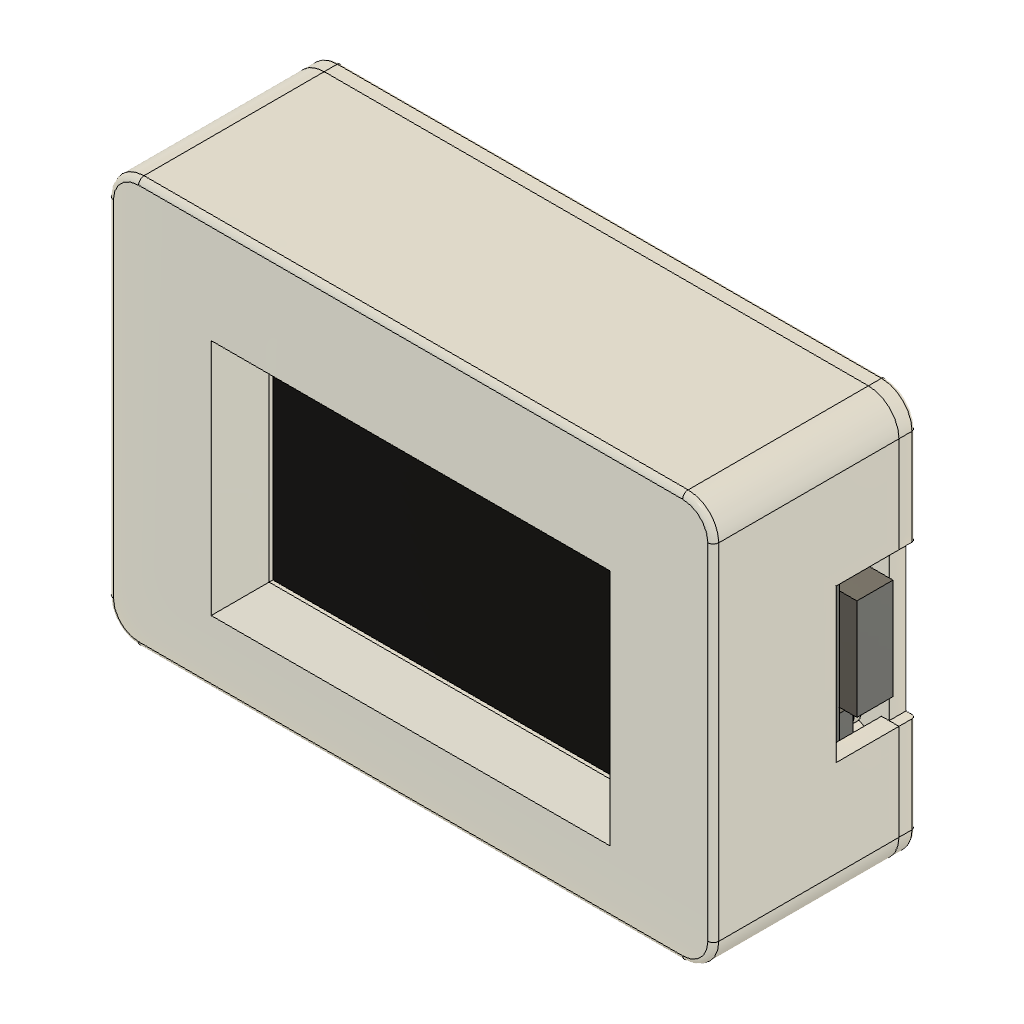
rocket-oled-tall-bezel-case (Autodesk Fusion 360 design; units mm, degrees)
part number: 2026-11-09-02-39-56-259
part number: 2026-11-09-02-39-56-642
part number: 2026-11-09-02-39-58-519
part number: 2026-11-09-02-40-05-044
part number: 2026-11-09-02-40-06-860
part number: 2026-11-09-02-56-29-701
part number: 2026-11-09-03-49-20-319
part number: 2026-11-09-03-49-23-306
part number: 2026-11-09-03-52-10-311
Autodesk Fusion 360 part; units mm, degrees
(part 1 of 3)
ref_plane "WorkPlane1" through (0, 0, 1.55) normal (0, 0, 1) x (1, 0, 0) in component "01 Beveled front - four blind OLED screw bosses"
sketch "Outer shell profile" plane through (0, 0, 1.55) normal (0, 0, 1) x (1, 0, 0) in component "01 Beveled front - four blind OLED screw bosses"
  line L0 (-27.71, -18.6) -> (27.71, -18.6)
  line L1 (27.71, -18.6) -> (27.71, 18.6)
  line L2 (27.71, 18.6) -> (-27.71, 18.6)
  line L3 (-27.71, 18.6) -> (-27.71, -18.6)
  dimension "d81" = 27.71
  dimension "d82" = 18.6
  dimension "d83" = 55.42
  dimension "d84" = 37.2
  constraint horizontal L0
  constraint horizontal L2
  constraint vertical L1
  constraint vertical L3
  measures "d81" horizontal distance of origin L0.start
  measures "d82" vertical distance of origin L0.start
  measures "d83" horizontal distance of L0.start L0.end
  measures "d84" vertical distance of L0.end L1.end
extrude "Outer shell" add sketch "Outer shell profile" along normal blind 17 makes body 1 in component "01 Beveled front - four blind OLED screw bosses"
fillet "Rounded exterior corners" radius 2.8 4 edges at (-27.71, 18.6, 10.05) (27.71, 18.6, 10.05) (27.71, -18.6, 10.05) (-27.71, -18.6, 10.05) on bodies 1 in component "01 Beveled front - four blind OLED screw bosses"
fillet "Soft front edge" radius 0.5 8 edges at (-26.8899, -17.7799, 18.55) (-27.71, 0, 18.55) (0, -18.6, 18.55) (26.8899, -17.7799, 18.55) (27.71, 0, 18.55) (26.8899, 17.7799, 18.55) (0, 18.6, 18.55) (-26.8899, 17.7799, 18.55) on bodies 1 in component "01 Beveled front - four blind OLED screw bosses"
ref_plane "WorkPlane2" through (0, 0, 1.55) normal (0, 0, 1) x (1, 0, 0) in component "01 Beveled front - four blind OLED screw bosses"
sketch "Open rear cavity profile" plane through (0, 0, 1.55) normal (0, 0, 1) x (1, 0, 0) in component "01 Beveled front - four blind OLED screw bosses"
  line L0 (-26.11, -17) -> (26.11, -17)
  line L1 (26.11, -17) -> (26.11, 17)
  line L2 (26.11, 17) -> (-26.11, 17)
  line L3 (-26.11, 17) -> (-26.11, -17)
  dimension "d93" = 26.11
  dimension "d94" = 17
  dimension "d95" = 52.22
  dimension "d96" = 34
  constraint horizontal L0
  constraint horizontal L2
  constraint vertical L1
  constraint vertical L3
  measures "d93" horizontal distance of origin L0.start
  measures "d94" vertical distance of origin L0.start
  measures "d95" horizontal distance of L0.start L0.end
  measures "d96" vertical distance of L0.end L1.end
extrude "Open rear cavity" cut sketch "Open rear cavity profile" along normal blind 12.4 bodies 1 in component "01 Beveled front - four blind OLED screw bosses"
fillet "Rounded cavity corners" radius 1.2 4 edges at (26.11, 17, 7.75) (-26.11, 17, 7.75) (26.11, -17, 7.75) (-26.11, -17, 7.75) on bodies 1 in component "01 Beveled front - four blind OLED screw bosses"
ref_plane "WorkPlane3" through (0, 0, 13.95) normal (0, 0, 1) x (1, 0, 0) in component "01 Beveled front - four blind OLED screw bosses"
sketch "OLED glass relief profile" plane through (0, 0, 13.95) normal (0, 0, 1) x (1, 0, 0) in component "01 Beveled front - four blind OLED screw bosses"
  line L0 (-17.55, -11.8) -> (17.55, -11.8)
  line L1 (17.55, -11.8) -> (17.55, 11.8)
  line L2 (17.55, 11.8) -> (-17.55, 11.8)
  line L3 (-17.55, 11.8) -> (-17.55, -11.8)
  dimension "d103" = 17.55
  dimension "d104" = 11.8
  dimension "d105" = 35.1
  dimension "d106" = 23.6
  constraint horizontal L0
  constraint horizontal L2
  constraint vertical L1
  constraint vertical L3
  measures "d103" horizontal distance of origin L0.start
  measures "d104" vertical distance of origin L0.start
  measures "d105" horizontal distance of L0.start L0.end
  measures "d106" vertical distance of L0.end L1.end
extrude "Glass clearance beneath concealed wiring bezel" cut sketch "OLED glass relief profile" along normal blind 1.6 bodies 1 in component "01 Beveled front - four blind OLED screw bosses"
ref_plane "WorkPlane4" through (0, 0, 15.55) normal (0, 0, 1) x (1, 0, 0) in component "01 Beveled front - four blind OLED screw bosses"
sketch "OLED active-area window profile" plane through (0, 0, 15.55) normal (0, 0, 1) x (1, 0, 0) in component "01 Beveled front - four blind OLED screw bosses"
  line L0 (-15.61, -10.05) -> (15.61, -10.05)
  line L1 (15.61, -10.05) -> (15.61, 6.45)
  line L2 (15.61, 6.45) -> (-15.61, 6.45)
  line L3 (-15.61, 6.45) -> (-15.61, -10.05)
  dimension "d111" = 15.61
  dimension "d112" = 10.05
  dimension "d113" = 31.22
  dimension "d114" = 16.5
  constraint horizontal L0
  constraint horizontal L2
  constraint vertical L1
  constraint vertical L3
  measures "d111" horizontal distance of origin L0.start
  measures "d112" vertical distance of origin L0.start
  measures "d113" horizontal distance of L0.start L0.end
  measures "d114" vertical distance of L0.end L1.end
ref_plane "WorkPlane5" through (0, 0, 13.45) normal (0, 0, 1) x (1, 0, 0) in component "01 Beveled front - four blind OLED screw bosses"
sketch "OLED PCB bearing pads 1 profile" plane through (0, 0, 13.45) normal (0, 0, 1) x (1, 0, 0) in component "01 Beveled front - four blind OLED screw bosses"
  circle A0 centre (-15.2, -14.25) radius 2.3
  dimension "d119" = 15.2
  dimension "d120" = 14.25
  dimension "d121" = 4.6
  measures "d119" horizontal distance of origin A0.centre
  measures "d120" vertical distance of origin A0.centre
  measures "d121" diameter of A0
extrude "OLED PCB bearing pads 1" add sketch "OLED PCB bearing pads 1 profile" along normal blind 0.5 bodies 1 in component "01 Beveled front - four blind OLED screw bosses"
ref_plane "WorkPlane6" through (0, 0, 13.45) normal (0, 0, 1) x (1, 0, 0) in component "01 Beveled front - four blind OLED screw bosses"
sketch "OLED PCB bearing pads 2 profile" plane through (0, 0, 13.45) normal (0, 0, 1) x (1, 0, 0) in component "01 Beveled front - four blind OLED screw bosses"
  circle A0 centre (-15.2, 14.25) radius 2.3
  dimension "d126" = 15.2
  dimension "d127" = 14.25
  dimension "d128" = 4.6
  measures "d126" horizontal distance of origin A0.centre
  measures "d127" vertical distance of origin A0.centre
  measures "d128" diameter of A0
extrude "OLED PCB bearing pads 2" add sketch "OLED PCB bearing pads 2 profile" along normal blind 0.5 bodies 1 in component "01 Beveled front - four blind OLED screw bosses"
ref_plane "WorkPlane7" through (0, 0, 13.45) normal (0, 0, 1) x (1, 0, 0) in component "01 Beveled front - four blind OLED screw bosses"
sketch "OLED PCB bearing pads 3 profile" plane through (0, 0, 13.45) normal (0, 0, 1) x (1, 0, 0) in component "01 Beveled front - four blind OLED screw bosses"
  circle A0 centre (15.2, -14.25) radius 2.3
  dimension "d133" = 15.2
  dimension "d134" = 14.25
  dimension "d135" = 4.6
  measures "d133" horizontal distance of origin A0.centre
  measures "d134" vertical distance of origin A0.centre
  measures "d135" diameter of A0
extrude "OLED PCB bearing pads 3" add sketch "OLED PCB bearing pads 3 profile" along normal blind 0.5 bodies 1 in component "01 Beveled front - four blind OLED screw bosses"
ref_plane "WorkPlane8" through (0, 0, 13.45) normal (0, 0, 1) x (1, 0, 0) in component "01 Beveled front - four blind OLED screw bosses"
sketch "OLED PCB bearing pads 4 profile" plane through (0, 0, 13.45) normal (0, 0, 1) x (1, 0, 0) in component "01 Beveled front - four blind OLED screw bosses"
  circle A0 centre (15.2, 14.25) radius 2.3
  dimension "d140" = 15.2
  dimension "d141" = 14.25
  dimension "d142" = 4.6
  measures "d140" horizontal distance of origin A0.centre
  measures "d141" vertical distance of origin A0.centre
  measures "d142" diameter of A0
extrude "OLED PCB bearing pads 4" add sketch "OLED PCB bearing pads 4 profile" along normal blind 0.5 bodies 1 in component "01 Beveled front - four blind OLED screw bosses"
ref_plane "WorkPlane9" through (0, 0, 11.9) normal (0, 0, 1) x (1, 0, 0) in component "01 Beveled front - four blind OLED screw bosses"
sketch "OLED left lower edge stop profile" plane through (0, 0, 11.9) normal (0, 0, 1) x (1, 0, 0) in component "01 Beveled front - four blind OLED screw bosses"
  line L0 (-19.45, -10.5) -> (-17.95, -10.5)
  line L1 (-17.95, -10.5) -> (-17.95, -6.5)
  line L2 (-17.95, -6.5) -> (-19.45, -6.5)
  line L3 (-19.45, -6.5) -> (-19.45, -10.5)
  dimension "d147" = 19.45
  dimension "d148" = 10.5
  dimension "d149" = 1.5
  dimension "d150" = 4
  constraint horizontal L0
  constraint horizontal L2
  constraint vertical L1
  constraint vertical L3
  measures "d147" horizontal distance of origin L0.start
  measures "d148" vertical distance of origin L0.start
  measures "d149" horizontal distance of L0.start L0.end
  measures "d150" vertical distance of L0.end L1.end
extrude "OLED left lower edge stop" add sketch "OLED left lower edge stop profile" along normal blind 2.05 bodies 1 in component "01 Beveled front - four blind OLED screw bosses"
ref_plane "WorkPlane10" through (0, 0, 11.9) normal (0, 0, 1) x (1, 0, 0) in component "01 Beveled front - four blind OLED screw bosses"
sketch "OLED left upper edge stop profile" plane through (0, 0, 11.9) normal (0, 0, 1) x (1, 0, 0) in component "01 Beveled front - four blind OLED screw bosses"
  line L0 (-19.45, 6.5) -> (-17.95, 6.5)
  line L1 (-17.95, 6.5) -> (-17.95, 10.5)
  line L2 (-17.95, 10.5) -> (-19.45, 10.5)
  line L3 (-19.45, 10.5) -> (-19.45, 6.5)
  dimension "d155" = 19.45
  dimension "d156" = 6.5
  dimension "d157" = 1.5
  dimension "d158" = 4
  constraint horizontal L0
  constraint horizontal L2
  constraint vertical L1
  constraint vertical L3
  measures "d155" horizontal distance of origin L0.start
  measures "d156" vertical distance of origin L0.start
  measures "d157" horizontal distance of L0.start L0.end
  measures "d158" vertical distance of L0.end L1.end
extrude "OLED left upper edge stop" add sketch "OLED left upper edge stop profile" along normal blind 2.05 bodies 1 in component "01 Beveled front - four blind OLED screw bosses"
ref_plane "WorkPlane11" through (0, 0, 11.9) normal (0, 0, 1) x (1, 0, 0) in component "01 Beveled front - four blind OLED screw bosses"
sketch "OLED right lower edge stop profile" plane through (0, 0, 11.9) normal (0, 0, 1) x (1, 0, 0) in component "01 Beveled front - four blind OLED screw bosses"
  line L0 (17.95, -10.5) -> (19.45, -10.5)
  line L1 (19.45, -10.5) -> (19.45, -6.5)
  line L2 (19.45, -6.5) -> (17.95, -6.5)
  line L3 (17.95, -6.5) -> (17.95, -10.5)
  dimension "d163" = 17.95
  dimension "d164" = 10.5
  dimension "d165" = 1.5
  dimension "d166" = 4
  constraint horizontal L0
  constraint horizontal L2
  constraint vertical L1
  constraint vertical L3
  measures "d163" horizontal distance of origin L0.start
  measures "d164" vertical distance of origin L0.start
  measures "d165" horizontal distance of L0.start L0.end
  measures "d166" vertical distance of L0.end L1.end
extrude "OLED right lower edge stop" add sketch "OLED right lower edge stop profile" along normal blind 2.05 bodies 1 in component "01 Beveled front - four blind OLED screw bosses"
ref_plane "WorkPlane12" through (0, 0, 11.9) normal (0, 0, 1) x (1, 0, 0) in component "01 Beveled front - four blind OLED screw bosses"
sketch "OLED right upper edge stop profile" plane through (0, 0, 11.9) normal (0, 0, 1) x (1, 0, 0) in component "01 Beveled front - four blind OLED screw bosses"
  line L0 (17.95, 6.5) -> (19.45, 6.5)
  line L1 (19.45, 6.5) -> (19.45, 10.5)
  line L2 (19.45, 10.5) -> (17.95, 10.5)
  line L3 (17.95, 10.5) -> (17.95, 6.5)
  dimension "d171" = 17.95
  dimension "d172" = 6.5
  dimension "d173" = 1.5
  dimension "d174" = 4
  constraint horizontal L0
  constraint horizontal L2
  constraint vertical L1
  constraint vertical L3
  measures "d171" horizontal distance of origin L0.start
  measures "d172" vertical distance of origin L0.start
  measures "d173" horizontal distance of L0.start L0.end
  measures "d174" vertical distance of L0.end L1.end
extrude "OLED right upper edge stop" add sketch "OLED right upper edge stop profile" along normal blind 2.05 bodies 1 in component "01 Beveled front - four blind OLED screw bosses"
ref_plane "WorkPlane13" through (0, 0, 6.85) normal (0, 0, 1) x (1, 0, 0) in component "01 Beveled front - four blind OLED screw bosses"
sketch "Shared M2 shell and ESP32 bosses 1 profile" plane through (0, 0, 6.85) normal (0, 0, 1) x (1, 0, 0) in component "01 Beveled front - four blind OLED screw bosses"
  circle A0 centre (-23.09, -11.2) radius 2.6
  dimension "d179" = 23.09
  dimension "d180" = 11.2
  dimension "d181" = 5.2
  measures "d179" horizontal distance of origin A0.centre
  measures "d180" vertical distance of origin A0.centre
  measures "d181" diameter of A0
extrude "Shared M2 shell and ESP32 bosses 1" add sketch "Shared M2 shell and ESP32 bosses 1 profile" along normal blind 7.1 bodies 1 in component "01 Beveled front - four blind OLED screw bosses"
ref_plane "WorkPlane14" through (0, 0, 6.85) normal (0, 0, 1) x (1, 0, 0) in component "01 Beveled front - four blind OLED screw bosses"
sketch "Shared M2 shell and ESP32 bosses 2 profile" plane through (0, 0, 6.85) normal (0, 0, 1) x (1, 0, 0) in component "01 Beveled front - four blind OLED screw bosses"
  circle A0 centre (-23.09, 11.2) radius 2.6
  dimension "d186" = 23.09
  dimension "d187" = 11.2
  dimension "d188" = 5.2
  measures "d186" horizontal distance of origin A0.centre
  measures "d187" vertical distance of origin A0.centre
  measures "d188" diameter of A0
extrude "Shared M2 shell and ESP32 bosses 2" add sketch "Shared M2 shell and ESP32 bosses 2 profile" along normal blind 7.1 bodies 1 in component "01 Beveled front - four blind OLED screw bosses"
ref_plane "WorkPlane15" through (0, 0, 6.85) normal (0, 0, 1) x (1, 0, 0) in component "01 Beveled front - four blind OLED screw bosses"
sketch "Shared M2 shell and ESP32 bosses 3 profile" plane through (0, 0, 6.85) normal (0, 0, 1) x (1, 0, 0) in component "01 Beveled front - four blind OLED screw bosses"
  circle A0 centre (23.09, -11.2) radius 2.6
  dimension "d193" = 23.09
  dimension "d194" = 11.2
  dimension "d195" = 5.2
  measures "d193" horizontal distance of origin A0.centre
  measures "d194" vertical distance of origin A0.centre
  measures "d195" diameter of A0
extrude "Shared M2 shell and ESP32 bosses 3" add sketch "Shared M2 shell and ESP32 bosses 3 profile" along normal blind 7.1 bodies 1 in component "01 Beveled front - four blind OLED screw bosses"
ref_plane "WorkPlane16" through (0, 0, 6.85) normal (0, 0, 1) x (1, 0, 0) in component "01 Beveled front - four blind OLED screw bosses"
sketch "Shared M2 shell and ESP32 bosses 4 profile" plane through (0, 0, 6.85) normal (0, 0, 1) x (1, 0, 0) in component "01 Beveled front - four blind OLED screw bosses"
  circle A0 centre (23.09, 11.2) radius 2.6
  dimension "d200" = 23.09
  dimension "d201" = 11.2
  dimension "d202" = 5.2
  measures "d200" horizontal distance of origin A0.centre
  measures "d201" vertical distance of origin A0.centre
  measures "d202" diameter of A0
extrude "Shared M2 shell and ESP32 bosses 4" add sketch "Shared M2 shell and ESP32 bosses 4 profile" along normal blind 7.1 bodies 1 in component "01 Beveled front - four blind OLED screw bosses"
ref_plane "WorkPlane17" through (0, 0, 6.85) normal (0, 0, 1) x (1, 0, 0) in component "01 Beveled front - four blind OLED screw bosses"
sketch "left lower screw boss reinforcement profile" plane through (0, 0, 6.85) normal (0, 0, 1) x (1, 0, 0) in component "01 Beveled front - four blind OLED screw bosses"
  line L0 (-26.31, -12.65) -> (-23.09, -12.65)
  line L1 (-23.09, -12.65) -> (-23.09, -9.75)
  line L2 (-23.09, -9.75) -> (-26.31, -9.75)
  line L3 (-26.31, -9.75) -> (-26.31, -12.65)
  dimension "d207" = 26.31
  dimension "d208" = 12.65
  dimension "d209" = 3.22
  dimension "d210" = 2.9
  constraint horizontal L0
  constraint horizontal L2
  constraint vertical L1
  constraint vertical L3
  measures "d207" horizontal distance of origin L0.start
  measures "d208" vertical distance of origin L0.start
  measures "d209" horizontal distance of L0.start L0.end
  measures "d210" vertical distance of L0.end L1.end
extrude "left lower screw boss reinforcement" add sketch "left lower screw boss reinforcement profile" along normal blind 7.1 bodies 1 in component "01 Beveled front - four blind OLED screw bosses"
ref_plane "WorkPlane18" through (0, 0, 6.85) normal (0, 0, 1) x (1, 0, 0) in component "01 Beveled front - four blind OLED screw bosses"
sketch "left upper screw boss reinforcement profile" plane through (0, 0, 6.85) normal (0, 0, 1) x (1, 0, 0) in component "01 Beveled front - four blind OLED screw bosses"
  line L0 (-26.31, 9.75) -> (-23.09, 9.75)
  line L1 (-23.09, 9.75) -> (-23.09, 12.65)
  line L2 (-23.09, 12.65) -> (-26.31, 12.65)
  line L3 (-26.31, 12.65) -> (-26.31, 9.75)
  dimension "d215" = 26.31
  dimension "d216" = 9.75
  dimension "d217" = 3.22
  dimension "d218" = 2.9
  constraint horizontal L0
  constraint horizontal L2
  constraint vertical L1
  constraint vertical L3
  measures "d215" horizontal distance of origin L0.start
  measures "d216" vertical distance of origin L0.start
  measures "d217" horizontal distance of L0.start L0.end
  measures "d218" vertical distance of L0.end L1.end
extrude "left upper screw boss reinforcement" add sketch "left upper screw boss reinforcement profile" along normal blind 7.1 bodies 1 in component "01 Beveled front - four blind OLED screw bosses"
ref_plane "WorkPlane19" through (0, 0, 6.85) normal (0, 0, 1) x (1, 0, 0) in component "01 Beveled front - four blind OLED screw bosses"
sketch "right lower screw boss reinforcement profile" plane through (0, 0, 6.85) normal (0, 0, 1) x (1, 0, 0) in component "01 Beveled front - four blind OLED screw bosses"
  line L0 (23.09, -12.65) -> (26.31, -12.65)
  line L1 (26.31, -12.65) -> (26.31, -9.75)
  line L2 (26.31, -9.75) -> (23.09, -9.75)
  line L3 (23.09, -9.75) -> (23.09, -12.65)
  dimension "d223" = 23.09
  dimension "d224" = 12.65
  dimension "d225" = 3.22
  dimension "d226" = 2.9
  constraint horizontal L0
  constraint horizontal L2
  constraint vertical L1
  constraint vertical L3
  measures "d223" horizontal distance of origin L0.start
  measures "d224" vertical distance of origin L0.start
  measures "d225" horizontal distance of L0.start L0.end
  measures "d226" vertical distance of L0.end L1.end
extrude "right lower screw boss reinforcement" add sketch "right lower screw boss reinforcement profile" along normal blind 7.1 bodies 1 in component "01 Beveled front - four blind OLED screw bosses"
ref_plane "WorkPlane20" through (0, 0, 6.85) normal (0, 0, 1) x (1, 0, 0) in component "01 Beveled front - four blind OLED screw bosses"
sketch "right upper screw boss reinforcement profile" plane through (0, 0, 6.85) normal (0, 0, 1) x (1, 0, 0) in component "01 Beveled front - four blind OLED screw bosses"
  line L0 (23.09, 9.75) -> (26.31, 9.75)
  line L1 (26.31, 9.75) -> (26.31, 12.65)
  line L2 (26.31, 12.65) -> (23.09, 12.65)
  line L3 (23.09, 12.65) -> (23.09, 9.75)
  dimension "d231" = 23.09
  dimension "d232" = 9.75
  dimension "d233" = 3.22
  dimension "d234" = 2.9
  constraint horizontal L0
  constraint horizontal L2
  constraint vertical L1
  constraint vertical L3
  measures "d231" horizontal distance of origin L0.start
  measures "d232" vertical distance of origin L0.start
  measures "d233" horizontal distance of L0.start L0.end
  measures "d234" vertical distance of L0.end L1.end
extrude "right upper screw boss reinforcement" add sketch "right upper screw boss reinforcement profile" along normal blind 7.1 bodies 1 in component "01 Beveled front - four blind OLED screw bosses"
ref_plane "WorkPlane21" through (0, 0, 6.85) normal (0, 0, 1) x (1, 0, 0) in component "01 Beveled front - four blind OLED screw bosses"
sketch "Blind M2 pilot 1 profile" plane through (0, 0, 6.85) normal (0, 0, 1) x (1, 0, 0) in component "01 Beveled front - four blind OLED screw bosses"
  circle A0 centre (-23.09, -11.2) radius 0.85
  dimension "d239" = 23.09
  dimension "d240" = 11.2
  dimension "d241" = 1.7
  measures "d239" horizontal distance of origin A0.centre
  measures "d240" vertical distance of origin A0.centre
  measures "d241" diameter of A0
extrude "Blind M2 pilot 1" cut sketch "Blind M2 pilot 1 profile" along normal blind 4.45 bodies 1 in component "01 Beveled front - four blind OLED screw bosses"
ref_plane "WorkPlane22" through (0, 0, 6.85) normal (0, 0, 1) x (1, 0, 0) in component "01 Beveled front - four blind OLED screw bosses"
sketch "Blind M2 pilot 2 profile" plane through (0, 0, 6.85) normal (0, 0, 1) x (1, 0, 0) in component "01 Beveled front - four blind OLED screw bosses"
  circle A0 centre (-23.09, 11.2) radius 0.85
  dimension "d246" = 23.09
  dimension "d247" = 11.2
  dimension "d248" = 1.7
  measures "d246" horizontal distance of origin A0.centre
  measures "d247" vertical distance of origin A0.centre
  measures "d248" diameter of A0
extrude "Blind M2 pilot 2" cut sketch "Blind M2 pilot 2 profile" along normal blind 4.45 bodies 1 in component "01 Beveled front - four blind OLED screw bosses"
ref_plane "WorkPlane23" through (0, 0, 6.85) normal (0, 0, 1) x (1, 0, 0) in component "01 Beveled front - four blind OLED screw bosses"
sketch "Blind M2 pilot 3 profile" plane through (0, 0, 6.85) normal (0, 0, 1) x (1, 0, 0) in component "01 Beveled front - four blind OLED screw bosses"
  circle A0 centre (23.09, -11.2) radius 0.85
  dimension "d253" = 23.09
  dimension "d254" = 11.2
  dimension "d255" = 1.7
  measures "d253" horizontal distance of origin A0.centre
  measures "d254" vertical distance of origin A0.centre
  measures "d255" diameter of A0
extrude "Blind M2 pilot 3" cut sketch "Blind M2 pilot 3 profile" along normal blind 4.45 bodies 1 in component "01 Beveled front - four blind OLED screw bosses"
ref_plane "WorkPlane24" through (0, 0, 6.85) normal (0, 0, 1) x (1, 0, 0) in component "01 Beveled front - four blind OLED screw bosses"
sketch "Blind M2 pilot 4 profile" plane through (0, 0, 6.85) normal (0, 0, 1) x (1, 0, 0) in component "01 Beveled front - four blind OLED screw bosses"
  circle A0 centre (23.09, 11.2) radius 0.85
  dimension "d260" = 23.09
  dimension "d261" = 11.2
  dimension "d262" = 1.7
  measures "d260" horizontal distance of origin A0.centre
  measures "d261" vertical distance of origin A0.centre
  measures "d262" diameter of A0
extrude "Blind M2 pilot 4" cut sketch "Blind M2 pilot 4 profile" along normal blind 4.45 bodies 1 in component "01 Beveled front - four blind OLED screw bosses"
ref_plane "WorkPlane25" through (0, 0, 1.55) normal (0, 0, 1) x (1, 0, 0) in component "01 Beveled front - four blind OLED screw bosses"
sketch "USB-C plug slot open at seam profile" plane through (0, 0, 1.55) normal (0, 0, 1) x (1, 0, 0) in component "01 Beveled front - four blind OLED screw bosses"
  line L0 (24.41, -7) -> (28.71, -7)
  line L1 (28.71, -7) -> (28.71, 7)
  line L2 (28.71, 7) -> (24.41, 7)
  line L3 (24.41, 7) -> (24.41, -7)
  dimension "d267" = 24.41
  dimension "d268" = 7
  dimension "d269" = 4.3
  dimension "d270" = 14
  constraint horizontal L0
  constraint horizontal L2
  constraint vertical L1
  constraint vertical L3
  measures "d267" horizontal distance of origin L0.start
  measures "d268" vertical distance of origin L0.start
  measures "d269" horizontal distance of L0.start L0.end
  measures "d270" vertical distance of L0.end L1.end
extrude "USB-C plug slot open at seam" cut sketch "USB-C plug slot open at seam profile" along normal blind 5.75 bodies 1 in component "01 Beveled front - four blind OLED screw bosses"
sketch "Flush rear plate profile" plane through (0, 0, 0) normal (0, 0, 1) x (1, 0, 0) in component "02 Rear cover - ESP32 mounting and concealed button access"
  line L0 (-27.71, -18.6) -> (27.71, -18.6)
  line L1 (27.71, -18.6) -> (27.71, 18.6)
  line L2 (27.71, 18.6) -> (-27.71, 18.6)
  line L3 (-27.71, 18.6) -> (-27.71, -18.6)
  dimension "d273" = 27.71
  dimension "d274" = 18.6
  dimension "d275" = 55.42
  dimension "d276" = 37.2
  constraint horizontal L0
  constraint horizontal L2
  constraint vertical L1
  constraint vertical L3
  measures "d273" horizontal distance of origin L0.start
  measures "d274" vertical distance of origin L0.start
  measures "d275" horizontal distance of L0.start L0.end
  measures "d276" vertical distance of L0.end L1.end
extrude "Flush rear plate" add sketch "Flush rear plate profile" along normal blind 1.55 separate body makes body 2 in component "02 Rear cover - ESP32 mounting and concealed button access"
fillet "Matched exterior corners" radius 2.8 4 edges at (-27.71, 18.6, 0.775) (27.71, 18.6, 0.775) (27.71, -18.6, 0.775) (-27.71, -18.6, 0.775) on bodies 2 in component "02 Rear cover - ESP32 mounting and concealed button access"
fillet "Soft rear edge" radius 0.35 8 edges at (-26.8899, -17.7799, 0) (-27.71, 0, 0) (26.8899, -17.7799, 0) (27.71, 0, 0) (26.8899, 17.7799, 0) (-26.8899, 17.7799, 0) (0, 18.6, 0) (0, -18.6, 0) on bodies 2 in component "02 Rear cover - ESP32 mounting and concealed button access"
ref_plane "WorkPlane1" through (0, 0, 1.55) normal (0, 0, 1) x (1, 0, 0) in component "02 Rear cover - ESP32 mounting and concealed button access"
sketch "Shared M2 screw recess feet 1 profile" plane through (0, 0, 1.55) normal (0, 0, 1) x (1, 0, 0) in component "02 Rear cover - ESP32 mounting and concealed button access"
  circle A0 centre (-23.09, -11.2) radius 3
  dimension "d285" = 23.09
  dimension "d286" = 11.2
  dimension "d287" = 6
  measures "d285" horizontal distance of origin A0.centre
  measures "d286" vertical distance of origin A0.centre
  measures "d287" diameter of A0
extrude "Shared M2 screw recess feet 1" add sketch "Shared M2 screw recess feet 1 profile" along normal blind 2 bodies 2 in component "02 Rear cover - ESP32 mounting and concealed button access"
ref_plane "WorkPlane2" through (0, 0, 1.55) normal (0, 0, 1) x (1, 0, 0) in component "02 Rear cover - ESP32 mounting and concealed button access"
sketch "Shared M2 screw recess feet 2 profile" plane through (0, 0, 1.55) normal (0, 0, 1) x (1, 0, 0) in component "02 Rear cover - ESP32 mounting and concealed button access"
  circle A0 centre (-23.09, 11.2) radius 3
  dimension "d292" = 23.09
  dimension "d293" = 11.2
  dimension "d294" = 6
  measures "d292" horizontal distance of origin A0.centre
  measures "d293" vertical distance of origin A0.centre
  measures "d294" diameter of A0
extrude "Shared M2 screw recess feet 2" add sketch "Shared M2 screw recess feet 2 profile" along normal blind 2 bodies 2 in component "02 Rear cover - ESP32 mounting and concealed button access"
ref_plane "WorkPlane3" through (0, 0, 1.55) normal (0, 0, 1) x (1, 0, 0) in component "02 Rear cover - ESP32 mounting and concealed button access"
sketch "Shared M2 screw recess feet 3 profile" plane through (0, 0, 1.55) normal (0, 0, 1) x (1, 0, 0) in component "02 Rear cover - ESP32 mounting and concealed button access"
  circle A0 centre (23.09, -11.2) radius 3
  dimension "d299" = 23.09
  dimension "d300" = 11.2
  dimension "d301" = 6
  measures "d299" horizontal distance of origin A0.centre
  measures "d300" vertical distance of origin A0.centre
  measures "d301" diameter of A0
extrude "Shared M2 screw recess feet 3" add sketch "Shared M2 screw recess feet 3 profile" along normal blind 2 bodies 2 in component "02 Rear cover - ESP32 mounting and concealed button access"
ref_plane "WorkPlane4" through (0, 0, 1.55) normal (0, 0, 1) x (1, 0, 0) in component "02 Rear cover - ESP32 mounting and concealed button access"
sketch "Shared M2 screw recess feet 4 profile" plane through (0, 0, 1.55) normal (0, 0, 1) x (1, 0, 0) in component "02 Rear cover - ESP32 mounting and concealed button access"
  circle A0 centre (23.09, 11.2) radius 3
  dimension "d306" = 23.09
  dimension "d307" = 11.2
  dimension "d308" = 6
  measures "d306" horizontal distance of origin A0.centre
  measures "d307" vertical distance of origin A0.centre
  measures "d308" diameter of A0
extrude "Shared M2 screw recess feet 4" add sketch "Shared M2 screw recess feet 4 profile" along normal blind 2 bodies 2 in component "02 Rear cover - ESP32 mounting and concealed button access"
ref_plane "WorkPlane5" through (0, 0, 3.55) normal (0, 0, 1) x (1, 0, 0) in component "02 Rear cover - ESP32 mounting and concealed button access"
sketch "ESP32 component-side mounting lands 1 profile" plane through (0, 0, 3.55) normal (0, 0, 1) x (1, 0, 0) in component "02 Rear cover - ESP32 mounting and concealed button access"
  circle A0 centre (-23.09, -11.2) radius 2.2
  dimension "d313" = 23.09
  dimension "d314" = 11.2
  dimension "d315" = 4.4
  measures "d313" horizontal distance of origin A0.centre
  measures "d314" vertical distance of origin A0.centre
  measures "d315" diameter of A0
extrude "ESP32 component-side mounting lands 1" add sketch "ESP32 component-side mounting lands 1 profile" along normal blind 1.6 bodies 2 in component "02 Rear cover - ESP32 mounting and concealed button access"
ref_plane "WorkPlane6" through (0, 0, 3.55) normal (0, 0, 1) x (1, 0, 0) in component "02 Rear cover - ESP32 mounting and concealed button access"
sketch "ESP32 component-side mounting lands 2 profile" plane through (0, 0, 3.55) normal (0, 0, 1) x (1, 0, 0) in component "02 Rear cover - ESP32 mounting and concealed button access"
  circle A0 centre (-23.09, 11.2) radius 2.2
  dimension "d320" = 23.09
  dimension "d321" = 11.2
  dimension "d322" = 4.4
  measures "d320" horizontal distance of origin A0.centre
  measures "d321" vertical distance of origin A0.centre
  measures "d322" diameter of A0
extrude "ESP32 component-side mounting lands 2" add sketch "ESP32 component-side mounting lands 2 profile" along normal blind 1.6 bodies 2 in component "02 Rear cover - ESP32 mounting and concealed button access"
ref_plane "WorkPlane7" through (0, 0, 3.55) normal (0, 0, 1) x (1, 0, 0) in component "02 Rear cover - ESP32 mounting and concealed button access"
sketch "ESP32 component-side mounting lands 3 profile" plane through (0, 0, 3.55) normal (0, 0, 1) x (1, 0, 0) in component "02 Rear cover - ESP32 mounting and concealed button access"
  circle A0 centre (23.09, -11.2) radius 2.2
  dimension "d327" = 23.09
  dimension "d328" = 11.2
  dimension "d329" = 4.4
  measures "d327" horizontal distance of origin A0.centre
  measures "d328" vertical distance of origin A0.centre
  measures "d329" diameter of A0
extrude "ESP32 component-side mounting lands 3" add sketch "ESP32 component-side mounting lands 3 profile" along normal blind 1.6 bodies 2 in component "02 Rear cover - ESP32 mounting and concealed button access"
ref_plane "WorkPlane8" through (0, 0, 3.55) normal (0, 0, 1) x (1, 0, 0) in component "02 Rear cover - ESP32 mounting and concealed button access"
sketch "ESP32 component-side mounting lands 4 profile" plane through (0, 0, 3.55) normal (0, 0, 1) x (1, 0, 0) in component "02 Rear cover - ESP32 mounting and concealed button access"
  circle A0 centre (23.09, 11.2) radius 2.2
  dimension "d334" = 23.09
  dimension "d335" = 11.2
  dimension "d336" = 4.4
  measures "d334" horizontal distance of origin A0.centre
  measures "d335" vertical distance of origin A0.centre
  measures "d336" diameter of A0
extrude "ESP32 component-side mounting lands 4" add sketch "ESP32 component-side mounting lands 4 profile" along normal blind 1.6 bodies 2 in component "02 Rear cover - ESP32 mounting and concealed button access"
sketch "Shared screws through rear cover 1 profile" plane through (0, 0, 0) normal (0, 0, 1) x (1, 0, 0) in component "02 Rear cover - ESP32 mounting and concealed button access"
  circle A0 centre (-23.09, -11.2) radius 1.175
  dimension "d339" = 23.09
  dimension "d340" = 11.2
  dimension "d341" = 2.35
  measures "d339" horizontal distance of origin A0.centre
  measures "d340" vertical distance of origin A0.centre
  measures "d341" diameter of A0
extrude "Shared screws through rear cover 1" cut sketch "Shared screws through rear cover 1 profile" along normal blind 5.15 bodies 2 in component "02 Rear cover - ESP32 mounting and concealed button access"
sketch "Shared screws through rear cover 2 profile" plane through (0, 0, 0) normal (0, 0, 1) x (1, 0, 0) in component "02 Rear cover - ESP32 mounting and concealed button access"
  circle A0 centre (-23.09, 11.2) radius 1.175
  dimension "d344" = 23.09
  dimension "d345" = 11.2
  dimension "d346" = 2.35
  measures "d344" horizontal distance of origin A0.centre
  measures "d345" vertical distance of origin A0.centre
  measures "d346" diameter of A0
extrude "Shared screws through rear cover 2" cut sketch "Shared screws through rear cover 2 profile" along normal blind 5.15 bodies 2 in component "02 Rear cover - ESP32 mounting and concealed button access"
sketch "Shared screws through rear cover 3 profile" plane through (0, 0, 0) normal (0, 0, 1) x (1, 0, 0) in component "02 Rear cover - ESP32 mounting and concealed button access"
  circle A0 centre (23.09, -11.2) radius 1.175
  dimension "d349" = 23.09
  dimension "d350" = 11.2
  dimension "d351" = 2.35
  measures "d349" horizontal distance of origin A0.centre
  measures "d350" vertical distance of origin A0.centre
  measures "d351" diameter of A0
extrude "Shared screws through rear cover 3" cut sketch "Shared screws through rear cover 3 profile" along normal blind 5.15 bodies 2 in component "02 Rear cover - ESP32 mounting and concealed button access"
sketch "Shared screws through rear cover 4 profile" plane through (0, 0, 0) normal (0, 0, 1) x (1, 0, 0) in component "02 Rear cover - ESP32 mounting and concealed button access"
  circle A0 centre (23.09, 11.2) radius 1.175
  dimension "d354" = 23.09
  dimension "d355" = 11.2
  dimension "d356" = 2.35
  measures "d354" horizontal distance of origin A0.centre
  measures "d355" vertical distance of origin A0.centre
  measures "d356" diameter of A0
extrude "Shared screws through rear cover 4" cut sketch "Shared screws through rear cover 4 profile" along normal blind 5.15 bodies 2 in component "02 Rear cover - ESP32 mounting and concealed button access"
sketch "Flush rear M2 head recess 1 profile" plane through (0, 0, 0) normal (0, 0, 1) x (1, 0, 0) in component "02 Rear cover - ESP32 mounting and concealed button access"
  circle A0 centre (-23.09, -11.2) radius 2.15
  dimension "d359" = 23.09
  dimension "d360" = 11.2
  dimension "d361" = 4.3
  measures "d359" horizontal distance of origin A0.centre
  measures "d360" vertical distance of origin A0.centre
  measures "d361" diameter of A0
extrude "Flush rear M2 head recess 1" cut sketch "Flush rear M2 head recess 1 profile" along normal blind 2.85 bodies 2 in component "02 Rear cover - ESP32 mounting and concealed button access"
sketch "Flush rear M2 head recess 2 profile" plane through (0, 0, 0) normal (0, 0, 1) x (1, 0, 0) in component "02 Rear cover - ESP32 mounting and concealed button access"
  circle A0 centre (-23.09, 11.2) radius 2.15
  dimension "d364" = 23.09
  dimension "d365" = 11.2
  dimension "d366" = 4.3
  measures "d364" horizontal distance of origin A0.centre
  measures "d365" vertical distance of origin A0.centre
  measures "d366" diameter of A0
extrude "Flush rear M2 head recess 2" cut sketch "Flush rear M2 head recess 2 profile" along normal blind 2.85 bodies 2 in component "02 Rear cover - ESP32 mounting and concealed button access"
sketch "Flush rear M2 head recess 3 profile" plane through (0, 0, 0) normal (0, 0, 1) x (1, 0, 0) in component "02 Rear cover - ESP32 mounting and concealed button access"
  circle A0 centre (23.09, -11.2) radius 2.15
  dimension "d369" = 23.09
  dimension "d370" = 11.2
  dimension "d371" = 4.3
  measures "d369" horizontal distance of origin A0.centre
  measures "d370" vertical distance of origin A0.centre
  measures "d371" diameter of A0
extrude "Flush rear M2 head recess 3" cut sketch "Flush rear M2 head recess 3 profile" along normal blind 2.85 bodies 2 in component "02 Rear cover - ESP32 mounting and concealed button access"
sketch "Flush rear M2 head recess 4 profile" plane through (0, 0, 0) normal (0, 0, 1) x (1, 0, 0) in component "02 Rear cover - ESP32 mounting and concealed button access"
  circle A0 centre (23.09, 11.2) radius 2.15
  dimension "d374" = 23.09
  dimension "d375" = 11.2
  dimension "d376" = 4.3
  measures "d374" horizontal distance of origin A0.centre
  measures "d375" vertical distance of origin A0.centre
  measures "d376" diameter of A0
extrude "Flush rear M2 head recess 4" cut sketch "Flush rear M2 head recess 4 profile" along normal blind 2.85 bodies 2 in component "02 Rear cover - ESP32 mounting and concealed button access"
ref_plane "WorkPlane9" through (0, 0, 1.55) normal (0, 0, 1) x (1, 0, 0) in component "02 Rear cover - ESP32 mounting and concealed button access"
sketch "BOOT tool guide profile" plane through (0, 0, 1.55) normal (0, 0, 1) x (1, 0, 0) in component "02 Rear cover - ESP32 mounting and concealed button access"
  circle A0 centre (22.86, -7.6) radius 1.4
  dimension "d381" = 22.86
  dimension "d383" = 2.8
  measures "d381" horizontal distance of origin A0.centre
  measures "d383" diameter of A0
extrude "BOOT tool guide" add sketch "BOOT tool guide profile" along normal blind 0.65 bodies 2 in component "02 Rear cover - ESP32 mounting and concealed button access"
sketch "BOOT recessed rear pinhole profile" plane through (0, 0, 0) normal (0, 0, 1) x (1, 0, 0) in component "02 Rear cover - ESP32 mounting and concealed button access"
  circle A0 centre (22.86, -7.6) radius 0.8
  dimension "d386" = 22.86
  dimension "d388" = 1.6
  measures "d386" horizontal distance of origin A0.centre
  measures "d388" diameter of A0
extrude "BOOT recessed rear pinhole" cut sketch "BOOT recessed rear pinhole profile" along normal blind 2.2 bodies 2 in component "02 Rear cover - ESP32 mounting and concealed button access"
ref_plane "WorkPlane10" through (0, 0, 1.55) normal (0, 0, 1) x (1, 0, 0) in component "02 Rear cover - ESP32 mounting and concealed button access"
sketch "EN tool guide profile" plane through (0, 0, 1.55) normal (0, 0, 1) x (1, 0, 0) in component "02 Rear cover - ESP32 mounting and concealed button access"
  circle A0 centre (22.86, 7.6) radius 1.4
  dimension "d393" = 22.86
  dimension "d395" = 2.8
  measures "d393" horizontal distance of origin A0.centre
  measures "d395" diameter of A0
extrude "EN tool guide" add sketch "EN tool guide profile" along normal blind 0.65 bodies 2 in component "02 Rear cover - ESP32 mounting and concealed button access"
sketch "EN recessed rear pinhole profile" plane through (0, 0, 0) normal (0, 0, 1) x (1, 0, 0) in component "02 Rear cover - ESP32 mounting and concealed button access"
  circle A0 centre (22.86, 7.6) radius 0.8
  dimension "d398" = 22.86
  dimension "d400" = 1.6
  measures "d398" horizontal distance of origin A0.centre
  measures "d400" diameter of A0
extrude "EN recessed rear pinhole" cut sketch "EN recessed rear pinhole profile" along normal blind 2.2 bodies 2 in component "02 Rear cover - ESP32 mounting and concealed button access"
ref_plane "WorkPlane11" through (0, 0, 1.55) normal (0, 0, 1) x (1, 0, 0) in component "02 Rear cover - ESP32 mounting and concealed button access"
sketch "OLED lower left retaining pad profile" plane through (0, 0, 1.55) normal (0, 0, 1) x (1, 0, 0) in component "02 Rear cover - ESP32 mounting and concealed button access"
  line L0 (-15.2, -16.76) -> (-10.4, -16.76)
  line L1 (-10.4, -16.76) -> (-10.4, -14.95)
  line L2 (-10.4, -14.95) -> (-15.2, -14.95)
  line L3 (-15.2, -14.95) -> (-15.2, -16.76)
  dimension "d405" = 15.2
  dimension "d407" = 4.8
  dimension "d408" = 1.81
  constraint horizontal L0
  constraint horizontal L2
  constraint vertical L1
  constraint vertical L3
  measures "d405" horizontal distance of origin L0.start
  measures "d407" horizontal distance of L0.start L0.end
  measures "d408" vertical distance of L0.end L1.end
ref_plane "WorkPlane12" through (0, 0, 1.55) normal (0, 0, 1) x (1, 0, 0) in component "02 Rear cover - ESP32 mounting and concealed button access"
sketch "OLED lower right retaining pad profile" plane through (0, 0, 1.55) normal (0, 0, 1) x (1, 0, 0) in component "02 Rear cover - ESP32 mounting and concealed button access"
  line L0 (10.4, -16.76) -> (15.2, -16.76)
  line L1 (15.2, -16.76) -> (15.2, -14.95)
  line L2 (15.2, -14.95) -> (10.4, -14.95)
  line L3 (10.4, -14.95) -> (10.4, -16.76)
  dimension "d413" = 10.4
  dimension "d415" = 4.8
  dimension "d416" = 1.81
  constraint horizontal L0
  constraint horizontal L2
  constraint vertical L1
  constraint vertical L3
  measures "d413" horizontal distance of origin L0.start
  measures "d415" horizontal distance of L0.start L0.end
  measures "d416" vertical distance of L0.end L1.end
ref_plane "WorkPlane13" through (0, 0, 1.55) normal (0, 0, 1) x (1, 0, 0) in component "02 Rear cover - ESP32 mounting and concealed button access"
sketch "OLED upper left retaining pad profile" plane through (0, 0, 1.55) normal (0, 0, 1) x (1, 0, 0) in component "02 Rear cover - ESP32 mounting and concealed button access"
  line L0 (-15.2, 14.95) -> (-10.4, 14.95)
  line L1 (-10.4, 14.95) -> (-10.4, 16.76)
  line L2 (-10.4, 16.76) -> (-15.2, 16.76)
  line L3 (-15.2, 16.76) -> (-15.2, 14.95)
  dimension "d421" = 15.2
  dimension "d423" = 4.8
  dimension "d424" = 1.81
  constraint horizontal L0
  constraint horizontal L2
  constraint vertical L1
  constraint vertical L3
  measures "d421" horizontal distance of origin L0.start
  measures "d423" horizontal distance of L0.start L0.end
  measures "d424" vertical distance of L0.end L1.end
ref_plane "WorkPlane14" through (0, 0, 1.55) normal (0, 0, 1) x (1, 0, 0) in component "02 Rear cover - ESP32 mounting and concealed button access"
sketch "OLED upper right retaining pad profile" plane through (0, 0, 1.55) normal (0, 0, 1) x (1, 0, 0) in component "02 Rear cover - ESP32 mounting and concealed button access"
  line L0 (10.4, 14.95) -> (15.2, 14.95)
  line L1 (15.2, 14.95) -> (15.2, 16.76)
  line L2 (15.2, 16.76) -> (10.4, 16.76)
  line L3 (10.4, 16.76) -> (10.4, 14.95)
  dimension "d429" = 10.4
  dimension "d431" = 4.8
  dimension "d432" = 1.81
  constraint horizontal L0
  constraint horizontal L2
  constraint vertical L1
  constraint vertical L3
  measures "d429" horizontal distance of origin L0.start
  measures "d431" horizontal distance of L0.start L0.end
  measures "d432" vertical distance of L0.end L1.end
ref_plane "WorkPlane15" through (0, 0, 1.55) normal (0, 0, 1) x (1, 0, 0) in component "02 Rear cover - ESP32 mounting and concealed button access"
sketch "ESP32 lower left registration stop profile" plane through (0, 0, 1.55) normal (0, 0, 1) x (1, 0, 0) in component "02 Rear cover - ESP32 mounting and concealed button access"
  line L0 (-18.5, -15.37) -> (-15.5, -15.37)
  line L1 (-15.5, -15.37) -> (-15.5, -14.17)
  line L2 (-15.5, -14.17) -> (-18.5, -14.17)
  line L3 (-18.5, -14.17) -> (-18.5, -15.37)
  dimension "d437" = 18.5
  dimension "d438" = 15.37
  dimension "d439" = 3
  dimension "d440" = 1.2
  constraint horizontal L0
  constraint horizontal L2
  constraint vertical L1
  constraint vertical L3
  measures "d437" horizontal distance of origin L0.start
  measures "d438" vertical distance of origin L0.start
  measures "d439" horizontal distance of L0.start L0.end
  measures "d440" vertical distance of L0.end L1.end
extrude "ESP32 lower left registration stop" add sketch "ESP32 lower left registration stop profile" along normal blind 5.1 bodies 2 in component "02 Rear cover - ESP32 mounting and concealed button access"
ref_plane "WorkPlane16" through (0, 0, 1.55) normal (0, 0, 1) x (1, 0, 0) in component "02 Rear cover - ESP32 mounting and concealed button access"
sketch "ESP32 lower right registration stop profile" plane through (0, 0, 1.55) normal (0, 0, 1) x (1, 0, 0) in component "02 Rear cover - ESP32 mounting and concealed button access"
  line L0 (15.5, -15.37) -> (18.5, -15.37)
  line L1 (18.5, -15.37) -> (18.5, -14.17)
  line L2 (18.5, -14.17) -> (15.5, -14.17)
  line L3 (15.5, -14.17) -> (15.5, -15.37)
  dimension "d445" = 15.5
  dimension "d446" = 15.37
  dimension "d447" = 3
  dimension "d448" = 1.2
  constraint horizontal L0
  constraint horizontal L2
  constraint vertical L1
  constraint vertical L3
  measures "d445" horizontal distance of origin L0.start
  measures "d446" vertical distance of origin L0.start
  measures "d447" horizontal distance of L0.start L0.end
  measures "d448" vertical distance of L0.end L1.end
extrude "ESP32 lower right registration stop" add sketch "ESP32 lower right registration stop profile" along normal blind 5.1 bodies 2 in component "02 Rear cover - ESP32 mounting and concealed button access"
ref_plane "WorkPlane17" through (0, 0, 1.55) normal (0, 0, 1) x (1, 0, 0) in component "02 Rear cover - ESP32 mounting and concealed button access"
sketch "ESP32 upper left registration stop profile" plane through (0, 0, 1.55) normal (0, 0, 1) x (1, 0, 0) in component "02 Rear cover - ESP32 mounting and concealed button access"
  line L0 (-18.5, 14.17) -> (-15.5, 14.17)
  line L1 (-15.5, 14.17) -> (-15.5, 15.37)
  line L2 (-15.5, 15.37) -> (-18.5, 15.37)
  line L3 (-18.5, 15.37) -> (-18.5, 14.17)
  dimension "d453" = 18.5
  dimension "d454" = 14.17
  dimension "d455" = 3
  dimension "d456" = 1.2
  constraint horizontal L0
  constraint horizontal L2
  constraint vertical L1
  constraint vertical L3
  measures "d453" horizontal distance of origin L0.start
  measures "d454" vertical distance of origin L0.start
  measures "d455" horizontal distance of L0.start L0.end
  measures "d456" vertical distance of L0.end L1.end
extrude "ESP32 upper left registration stop" add sketch "ESP32 upper left registration stop profile" along normal blind 5.1 bodies 2 in component "02 Rear cover - ESP32 mounting and concealed button access"
ref_plane "WorkPlane18" through (0, 0, 1.55) normal (0, 0, 1) x (1, 0, 0) in component "02 Rear cover - ESP32 mounting and concealed button access"
sketch "ESP32 upper right registration stop profile" plane through (0, 0, 1.55) normal (0, 0, 1) x (1, 0, 0) in component "02 Rear cover - ESP32 mounting and concealed button access"
  line L0 (15.5, 14.17) -> (18.5, 14.17)
  line L1 (18.5, 14.17) -> (18.5, 15.37)
  line L2 (18.5, 15.37) -> (15.5, 15.37)
  line L3 (15.5, 15.37) -> (15.5, 14.17)
  dimension "d461" = 15.5
  dimension "d462" = 14.17
  dimension "d463" = 3
  dimension "d464" = 1.2
  constraint horizontal L0
  constraint horizontal L2
  constraint vertical L1
  constraint vertical L3
  measures "d461" horizontal distance of origin L0.start
  measures "d462" vertical distance of origin L0.start
  measures "d463" horizontal distance of L0.start L0.end
  measures "d464" vertical distance of L0.end L1.end
extrude "ESP32 upper right registration stop" add sketch "ESP32 upper right registration stop profile" along normal blind 5.1 bodies 2 in component "02 Rear cover - ESP32 mounting and concealed button access"
ref_plane "WorkPlane19" through (0, 0, 1.55) normal (0, 0, 1) x (1, 0, 0) in component "02 Rear cover - ESP32 mounting and concealed button access"
sketch "left lower rear registration key profile" plane through (0, 0, 1.55) normal (0, 0, 1) x (1, 0, 0) in component "02 Rear cover - ESP32 mounting and concealed button access"
  line L0 (-25.86, -15.45) -> (-24.61, -15.45)
  line L1 (-24.61, -15.45) -> (-24.61, -12.85)
  line L2 (-24.61, -12.85) -> (-25.86, -12.85)
  line L3 (-25.86, -12.85) -> (-25.86, -15.45)
  dimension "d469" = 25.86
  dimension "d470" = 15.45
  dimension "d471" = 1.25
  dimension "d472" = 2.6
  constraint horizontal L0
  constraint horizontal L2
  constraint vertical L1
  constraint vertical L3
  measures "d469" horizontal distance of origin L0.start
  measures "d470" vertical distance of origin L0.start
  measures "d471" horizontal distance of L0.start L0.end
  measures "d472" vertical distance of L0.end L1.end
extrude "left lower rear registration key" add sketch "left lower rear registration key profile" along normal blind 1.15 bodies 2 in component "02 Rear cover - ESP32 mounting and concealed button access"
ref_plane "WorkPlane20" through (0, 0, 1.55) normal (0, 0, 1) x (1, 0, 0) in component "02 Rear cover - ESP32 mounting and concealed button access"
sketch "left upper rear registration key profile" plane through (0, 0, 1.55) normal (0, 0, 1) x (1, 0, 0) in component "02 Rear cover - ESP32 mounting and concealed button access"
  line L0 (-25.86, 12.85) -> (-24.61, 12.85)
  line L1 (-24.61, 12.85) -> (-24.61, 15.45)
  line L2 (-24.61, 15.45) -> (-25.86, 15.45)
  line L3 (-25.86, 15.45) -> (-25.86, 12.85)
  dimension "d477" = 25.86
  dimension "d478" = 12.85
  dimension "d479" = 1.25
  dimension "d480" = 2.6
  constraint horizontal L0
  constraint horizontal L2
  constraint vertical L1
  constraint vertical L3
  measures "d477" horizontal distance of origin L0.start
  measures "d478" vertical distance of origin L0.start
  measures "d479" horizontal distance of L0.start L0.end
  measures "d480" vertical distance of L0.end L1.end
extrude "left upper rear registration key" add sketch "left upper rear registration key profile" along normal blind 1.15 bodies 2 in component "02 Rear cover - ESP32 mounting and concealed button access"